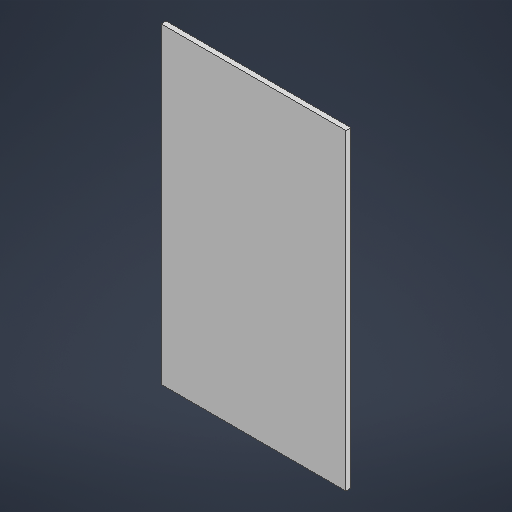
# Autodesk Inventor part: Circuit board
Saved by Autodesk Inventor 2026.2 (Build 302298010, 298A)
## iProperties
Created: 2026-10-04
Part Number: Circuit board
Material: Generisch
Document SubType Name: Modeling
Designer: denis
Mass: 148 g
Surface Area: 771.84 cm^2
Volume: 148 cm^3
Density: 1 g/cm^3
Appearance: Vorgabe
Author: denis
Autodesk Inventor part; units mm, degrees
ref_plane "YZ Plane" through (0, 0, 0) normal (1, 0, 0) x (0, 1, 0)
ref_plane "XZ Plane" through (0, 0, 0) normal (0, 1, 0) x (-1, 0, 0)
ref_plane "XY Plane" through (0, 0, 0) normal (0, 0, 1) x (1, 0, 0)
sketch "Skizze1" plane through (0, 0, 0) normal (0, 0, 1) x (1, 0, 0)
  line L0 (0, -175) -> (0, 175) construction
  line L1 (-103.6, 0) -> (103.6, 0) construction
  line L2 (-74, 125) -> (74, 125)
  line L3 (74, 125) -> (74, -125)
  line L4 (74, -125) -> (-74, -125)
  line L5 (-74, -125) -> (-74, 125)
  line L6 (-74, 125) -> (74, -125) construction
  line L7 (74, 125) -> (-74, -125) construction
  point P0 (0, 0)
  dimension "d0" = 148
  dimension "d1" = 250
  constraints: 12 end point, 2 midpoint, 2 parallel, 1 horizontal, 1 perpendicular
  measures "d0" distance of L3.end L4.end
  measures "d1" distance of L2.end L3.end
extrude "Extrusion1" add sketch "Skizze1" along normal blind 4
